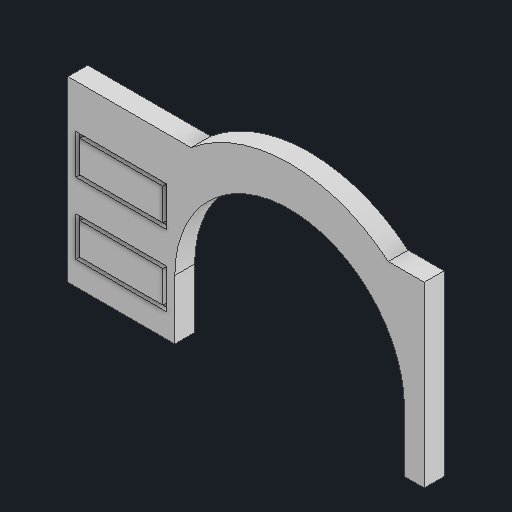
# Autodesk Inventor part: 7_1_5_tour_roue_avant_droite
Saved by Autodesk Inventor 2026 (Build 300175000, 175)
## iProperties
Created: 2025-06-21
Part Number: 7_1_5_tour_roue_avant_droite
Material: Generic
Document SubType Name: Modeling
Designer: remg9
Density: 1 g/cm^3
Appearance: Default
Author: remg9
Autodesk Inventor part; units mm, degrees
ref_plane "YZ Plane" through (0, 0, 0) normal (1, 0, 0) x (0, 1, 0)
ref_plane "XZ Plane" through (0, 0, 0) normal (0, 1, 0) x (-1, 0, 0)
ref_plane "XY Plane" through (0, 0, 0) normal (0, 0, 1) x (1, 0, 0)
sketch "Sketch1" plane through (0, 0, 0) normal (0, 0, 1) x (1, 0, 0)
  line L0 (0, 0) -> (27, 0)
  line L1 (31.0801, 45) -> (0, 45)
  line L2 (0, 45) -> (0, 0)
  line L3 (27, 15) -> (85, 15) construction
  line L4 (85, 15) -> (85, 0) construction
  arc A0 (85, 15) -> (27, 15) centre (56, 15) ccw
  arc A1 (80.9199, 45) -> (31.0801, 45) centre (56, 15) ccw
  line L5 (27, 0) -> (27, 15)
  line L6 (80.9199, 45) -> (90, 45)
  line L7 (90, 45) -> (90, 0)
  line L8 (90, 0) -> (85, 0)
  line L9 (85, 0) -> (85, 15)
  dimension "d0" = 15
  dimension "d2" = 29
  dimension "d4" = 5
  dimension "d5" = 27
  dimension "d6" = 45
  dimension "d7" = 39
  constraints: 20 end point, 4 point on circle, 3 perpendicular, 2 centre point, 2 collinear, 2 horizontal, 2 vertical, 1 coincident, 1 midpoint, 1 parallel
  measures "d0" distance between parallel lines of L0 L3
  measures "d2" radius of A0
  measures "d4" distance of L7.end L4.end
  measures "d5" distance of L0.start L0.end
  measures "d6" distance between parallel lines of L0 L1
  measures "d7" radius of A1
extrude "Extrusion1" add sketch "Sketch1" along normal blind 5
sketch "Sketch2" plane through (0, 0, 5) normal (0, 0, 1) x (1, 0, 0)
  line L0 (2, 34) -> (25, 34)
  line L1 (25, 34) -> (25, 24)
  line L2 (25, 24) -> (2, 24)
  line L3 (2, 24) -> (2, 34)
  line L4 (3, 33) -> (24, 33)
  line L5 (24, 33) -> (24, 25)
  line L6 (24, 25) -> (3, 25)
  line L7 (3, 25) -> (3, 33)
  line L8 (2, 16) -> (25, 16)
  line L9 (25, 16) -> (25, 6)
  line L10 (25, 6) -> (2, 6)
  line L11 (2, 6) -> (2, 16)
  line L12 (3, 15) -> (24, 15)
  line L13 (24, 15) -> (24, 7)
  line L14 (24, 7) -> (3, 7)
  line L15 (3, 7) -> (3, 15)
  line L16 (0, 45) -> (0, 0) projected
  line L17 (27, 0) -> (27, 15) projected
  line L18 (0, 0) -> (27, 0) projected
  dimension "d10" = 2
  dimension "d11" = 2
  dimension "d12" = 1
  dimension "d13" = 1
  dimension "d14" = 1
  dimension "d15" = 1
  dimension "d16" = 1
  dimension "d17" = 1
  dimension "d18" = 6
  dimension "d19" = 8
  dimension "d20" = 10
  dimension "d21" = 10
  constraints: 32 end point, 8 parallel, 4 horizontal, 4 perpendicular, 4 point on line
  measures "d10" distance between parallel lines of L16 L3
  measures "d11" distance between parallel lines of L17 L9
  measures "d12" distance between parallel lines of L11 L15
  measures "d13" distance between parallel lines of L9 L13
  measures "d14" distance between parallel lines of L8 L12
  measures "d15" distance between parallel lines of L10 L14
  measures "d16" distance between parallel lines of L0 L4
  measures "d17" distance between parallel lines of L2 L6
  measures "d18" distance between parallel lines of L18 L10
  measures "d19" distance between parallel lines of L2 L8
  measures "d20" distance of L8.end L9.end
  measures "d21" distance of L0.end L1.end
extrude "Extrusion2" cut sketch "Sketch2" against normal blind 1
body "Solid1"
